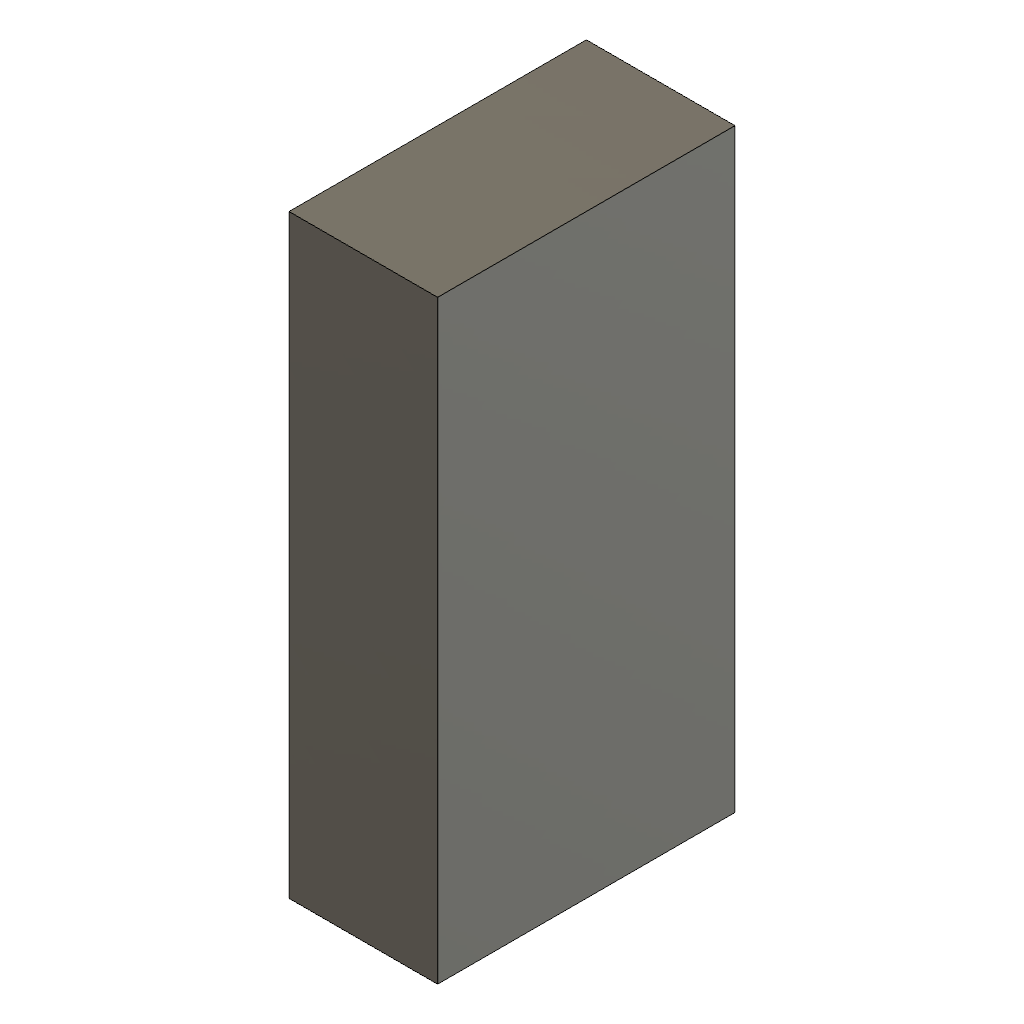
P03-fusion-plane-yz (Autodesk Fusion 360 design; units mm, degrees)
part number: 2026-11-14-20-01-36-655
Autodesk Fusion 360 part; units mm, degrees
sketch "RectangleSketch" plane through (0, 0, 0) normal (1, 0, 0) x (0, 0, -1)
  line L0 (0, 0) -> (0, 40)
  line L1 (0, 40) -> (-20, 40)
  line L2 (-20, 40) -> (-20, 0)
  line L3 (-20, 0) -> (0, 0)
  dimension "width_mm" = 40
  dimension "height_mm" = 20
  constraint vertical L0
  constraint horizontal L1
  constraint vertical L2
  constraint horizontal L3
  constraint coincident L0.start L3.end
  measures "width_mm" vertical distance of L0.start L0.end
  measures "height_mm" horizontal distance of L0.start L2.end
extrude "BlindBoss" add sketch "RectangleSketch" along normal blind 10
equation "depth_mm = 10 mm"
